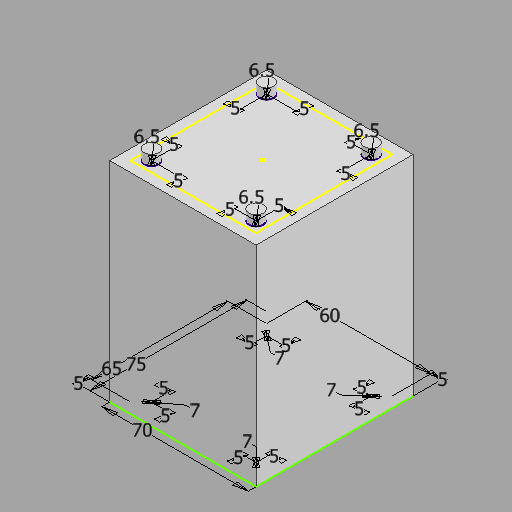
# Autodesk Inventor part: Z1
Saved by Autodesk Inventor 2027 (Build 310192000, 192)
## iProperties
Created: 2026-09-16
Part Number: Z1
Material: Generic
Document SubType Name: Modeling
Designer: jyjhm
Density: 1 g/cm^3
Appearance: Default
Author: jyjhm
Autodesk Inventor part; units mm, degrees
ref_plane "YZ Plane" through (0, 0, 0) normal (1, 0, 0) x (0, 1, 0)
ref_plane "XZ Plane" through (0, 0, 0) normal (0, 1, 0) x (-1, 0, 0)
ref_plane "XY Plane" through (0, 0, 0) normal (0, 0, 1) x (1, 0, 0)
sketch "Sketch1" plane through (0, 0, 0) normal (0, 1, 0) x (-1, 0, 0)
  line L0 (36.6667, 36.6667) -> (-33.3333, 36.6667)
  line L1 (-33.3333, 36.6667) -> (-33.3333, -38.3333)
  line L2 (-33.3333, -38.3333) -> (36.6667, -38.3333)
  line L3 (36.6667, -38.3333) -> (36.6667, 36.6667)
  line L4 (31.6667, 31.6667) -> (-28.3333, 31.6667)
  line L5 (-28.3333, 31.6667) -> (-28.3333, -33.3333)
  line L6 (-28.3333, -33.3333) -> (31.6667, -33.3333)
  line L7 (31.6667, -33.3333) -> (31.6667, 31.6667)
  circle A0 centre (26.6667, 26.6667) radius 3.5
  circle A1 centre (26.6667, -28.3333) radius 3.5
  circle A2 centre (-23.3333, -28.3333) radius 3.5
  circle A3 centre (-23.3333, 26.6667) radius 3.5
  point P0 (0, 0)
  dimension "d0" = 70
  dimension "d1" = 75
  dimension "d2" = 65
  dimension "d3" = 5
  dimension "d4" = 60
  dimension "d5" = 5
  dimension "d6" = 5
  dimension "d7" = 5
  dimension "d8" = 5
  dimension "d9" = 5
  dimension "d10" = 5
  dimension "d11" = 5
  dimension "d12" = 5
  dimension "d13" = 5
  dimension "d27" = 7
  dimension "d28" = 7
  dimension "d29" = 7
  dimension "d30" = 7
  constraints: 16 end point, 4 centre point, 4 parallel, 2 horizontal, 2 perpendicular
  measures "d0" distance of L0.start L0.end
  measures "d1" distance of L2.end L0.start
  measures "d2" distance of L6.end L4.start
  measures "d3" distance between parallel lines of L0 L4
  measures "d4" distance of L5.end L6.end
  measures "d5" distance between parallel lines of L1 L5
  measures "d6" distance from line of L7 A0.centre
  measures "d7" distance from line of L4 A0.centre
  measures "d8" distance from line of L5 A3.centre
  measures "d9" distance from line of L4 A3.centre
  measures "d10" distance from line of L6 A2.centre
  measures "d11" distance from line of L5 A2.centre
  measures "d12" distance from line of L6 A1.centre
  measures "d13" distance from line of L7 A1.centre
  measures "d27" diameter of A3
  measures "d28" diameter of A0
  measures "d29" diameter of A2
  measures "d30" diameter of A1
extrude "Extrusion1" add sketch "Sketch1" along normal blind 10 contours L3 L2 L1 L0 | L7 L6 L5 L4 | A0 | A1 | A2 | A3
extrude "Extrusion2" add sketch "Sketch1" along normal blind 100 contours L3 L2 L1 L0
sketch "Sketch2" plane through (0, 100, 0) normal (0, 1, 0) x (1, 0, 0)
  line L0 (33.3333, -36.6667) -> (33.3333, 38.3333) projected
  line L1 (33.3333, 38.3333) -> (-36.6667, 38.3333) projected
  line L2 (-36.6667, 38.3333) -> (-36.6667, -36.6667) projected
  line L3 (-36.6667, -36.6667) -> (33.3333, -36.6667) projected
  line L4 (-31.6667, -31.6667) -> (-31.6667, 33.3333) projected
  line L5 (-31.6667, 33.3333) -> (28.3333, 33.3333) projected
  line L6 (28.3333, 33.3333) -> (28.3333, -31.6667) projected
  line L7 (28.3333, -31.6667) -> (-31.6667, -31.6667) projected
  line L8 (-31.6667, -31.6667) -> (28.3333, -31.6667) projected
  line L9 (28.3333, -31.6667) -> (28.3333, 33.3333) projected
  line L10 (28.3333, 33.3333) -> (-31.6667, 33.3333) projected
  line L11 (-31.6667, 33.3333) -> (-31.6667, -31.6667) projected
  point P0 (0, 0)
extrude "Extrusion3" add sketch "Sketch2" against normal blind 10 contours L3 L2 L1 L0 | L4 L5 L6 L7
extrude "Extrusion4" cut sketch "Sketch1" along normal blind 5 contours A0 | A1 | A2 | A3
sketch "Sketch4" plane through (0, 100, 0) normal (0, 1, 0) x (1, 0, 0)
  line L0 (33.3333, 38.3333) -> (-36.6667, 38.3333) projected
  line L1 (-36.6667, 38.3333) -> (-36.6667, -36.6667) projected
  line L2 (-36.6667, 38.3333) -> (-36.6667, -36.6667) projected
  line L3 (33.3333, 38.3333) -> (-36.6667, 38.3333) projected
  line L4 (-31.6667, 33.3333) -> (-31.6667, -31.6667) projected
  line L5 (-31.6667, 33.3333) -> (-31.6667, -31.6667) projected
  line L6 (-31.6667, -31.6667) -> (28.3333, -31.6667) projected
  line L7 (-31.6667, -31.6667) -> (28.3333, -31.6667) projected
  line L8 (28.3333, 33.3333) -> (-31.6667, 33.3333) projected
  line L9 (28.3333, 33.3333) -> (-31.6667, 33.3333) projected
  line L10 (28.3333, -31.6667) -> (28.3333, 33.3333) projected
  line L11 (28.3333, -31.6667) -> (28.3333, 33.3333) projected
  line L12 (-36.6667, 38.3333) -> (-36.6667, -36.6667) projected
  line L13 (-36.6667, 38.3333) -> (-36.6667, -36.6667) projected
  line L14 (33.3333, 38.3333) -> (-36.6667, 38.3333) projected
  line L15 (33.3333, 38.3333) -> (-36.6667, 38.3333) projected
  line L16 (33.3333, -36.6667) -> (33.3333, 38.3333) projected
  line L17 (33.3333, -36.6667) -> (33.3333, 38.3333) projected
  line L18 (-36.6667, -36.6667) -> (33.3333, -36.6667) projected
  line L19 (-36.6667, -36.6667) -> (33.3333, -36.6667) projected
  line L20 (33.3333, -36.6667) -> (33.3333, 38.3333) projected
  line L21 (33.3333, 38.3333) -> (-36.6667, 38.3333) projected
  line L22 (-36.6667, 38.3333) -> (-36.6667, -36.6667) projected
  line L23 (-36.6667, -36.6667) -> (33.3333, -36.6667) projected
  line L24 (33.3333, -36.6667) -> (33.3333, 38.3333) projected
  line L25 (-36.6667, -36.6667) -> (33.3333, -36.6667) projected
  line L26 (-31.6667, 33.3333) -> (-31.6667, -31.6667) projected
  line L27 (-31.6667, -31.6667) -> (28.3333, -31.6667) projected
  line L28 (28.3333, 33.3333) -> (-31.6667, 33.3333) projected
  line L29 (28.3333, -31.6667) -> (28.3333, 33.3333) projected
  line L30 (28.3333, -31.6667) -> (28.3333, 33.3333) projected
  line L31 (-31.6667, -31.6667) -> (28.3333, -31.6667) projected
  line L32 (-31.6667, 33.3333) -> (-31.6667, -31.6667) projected
  line L33 (28.3333, 33.3333) -> (-31.6667, 33.3333) projected
  line L34 (-31.6667, -31.6667) -> (28.3333, -31.6667) projected
  line L35 (28.3333, -31.6667) -> (28.3333, 33.3333) projected
  circle A0 centre (-26.6667, -26.6667) radius 3.5 projected
  circle A1 centre (-26.6667, -26.6667) radius 3.5 projected
  circle A2 centre (-26.6667, -26.6667) radius 3.5 projected
  circle A3 centre (-26.6667, 28.3333) radius 3.5 projected
  circle A4 centre (23.3333, 28.3333) radius 3.5 projected
  circle A5 centre (23.3333, 28.3333) radius 3.5 projected
  line L36 (33.3333, -36.6667) -> (33.3333, 38.3333) projected
  circle A6 centre (-26.6667, 28.3333) radius 3.5 projected
  circle A7 centre (23.3333, 28.3333) radius 3.5 projected
  circle A8 centre (-26.6667, -26.6667) radius 3.5 projected
  circle A9 centre (23.3333, -26.6667) radius 3.5 projected
  line L37 (33.3333, -36.6667) -> (33.3333, 38.3333) projected
  line L38 (-36.6667, -36.6667) -> (33.3333, -36.6667) projected
  line L39 (-36.6667, 38.3333) -> (-36.6667, -36.6667) projected
  line L40 (33.3333, 38.3333) -> (-36.6667, 38.3333) projected
  line L41 (-36.6667, -36.6667) -> (33.3333, -36.6667) projected
  line L42 (-31.6667, -31.6667) -> (28.3333, -31.6667) projected
  line L43 (28.3333, -31.6667) -> (28.3333, 33.3333) projected
  line L44 (28.3333, 33.3333) -> (-31.6667, 33.3333) projected
  line L45 (-31.6667, 33.3333) -> (-31.6667, -31.6667) projected
  line L46 (-31.6667, 33.3333) -> (-31.6667, -31.6667) projected
  circle A10 centre (-26.6667, -26.6667) radius 3.5 projected
  circle A11 centre (-26.6667, -26.6667) radius 3.5 projected
  circle A12 centre (23.3333, -26.6667) radius 3.5 projected
  circle A13 centre (23.3333, -26.6667) radius 3.5 projected
  circle A14 centre (23.3333, -26.6667) radius 3.5 projected
  circle A15 centre (23.3333, -26.6667) radius 3.5 projected
  circle A16 centre (23.3333, -26.6667) radius 3.5 projected
  line L47 (28.3333, 33.3333) -> (-31.6667, 33.3333) projected
  circle A17 centre (23.3333, 28.3333) radius 3.5 projected
  circle A18 centre (23.3333, 28.3333) radius 3.5 projected
  circle A19 centre (23.3333, 28.3333) radius 3.5 projected
  circle A20 centre (-26.6667, 28.3333) radius 3.5 projected
  circle A21 centre (-26.6667, 28.3333) radius 3.5 projected
  circle A22 centre (-26.6667, 28.3333) radius 3.5 projected
  circle A23 centre (-26.6667, 28.3333) radius 3.5 projected
  circle A24 centre (-26.6667, 28.3333) radius 3.5 projected
  circle A25 centre (23.3333, -26.6667) radius 3.5 projected
  line L48 (-31.6667, -31.6667) -> (28.3333, -31.6667) projected
  line L49 (28.3333, -31.6667) -> (28.3333, 33.3333) projected
  line L50 (33.3333, -36.6667) -> (33.3333, 38.3333) projected
  line L51 (-36.6667, -36.6667) -> (33.3333, -36.6667) projected
  circle A26 centre (-26.6667, -26.6667) radius 3.5 projected
  line L52 (-31.6667, 33.3333) -> (-31.6667, -31.6667) projected
  line L53 (-36.6667, 38.3333) -> (-36.6667, -36.6667) projected
  circle A27 centre (23.3333, 28.3333) radius 3.5 projected
  line L54 (33.3333, 38.3333) -> (-36.6667, 38.3333) projected
  line L55 (28.3333, 33.3333) -> (-31.6667, 33.3333) projected
  point P0 (0, 0)
  point P1 (0, 0)
  constraints: 20 other
sketch "Sketch5" plane through (0, 100, 0) normal (0, 1, 0) x (1, 0, 0)
  circle A0 centre (23.3333, -26.6667) radius 3.25
  line L0 (-31.6667, -31.6667) -> (28.3333, -31.6667) projected
  line L1 (28.3333, -31.6667) -> (28.3333, 33.3333) projected
  circle A1 centre (-26.6667, -26.6667) radius 3.25
  circle A2 centre (23.3333, 28.3333) radius 3.25
  circle A3 centre (-26.6667, 28.3333) radius 3.25
  line L2 (-31.6667, 33.3333) -> (-31.6667, -31.6667) projected
  line L3 (28.3333, 33.3333) -> (-31.6667, 33.3333) projected
  point P0 (0, 0)
  dimension "d24" = 5
  dimension "d25" = 5
  dimension "d26" = 6.5
  dimension "d31" = 6.5
  dimension "d32" = 6.5
  dimension "d33" = 6.5
  dimension "d34" = 5
  dimension "d35" = 5
  dimension "d36" = 5
  dimension "d37" = 5
  dimension "d38" = 5
  dimension "d39" = 5
  constraints: 4 centre point
  measures "d24" distance from line of L0 A0.centre
  measures "d25" distance from line of L1 A0.centre
  measures "d26" diameter of A0
  measures "d31" diameter of A1
  measures "d32" diameter of A2
  measures "d33" diameter of A3
  measures "d34" distance from line of L0 A1.centre
  measures "d35" distance from line of L2 A1.centre
  measures "d36" distance from line of L2 A3.centre
  measures "d37" distance from line of L3 A3.centre
  measures "d38" distance from line of L3 A2.centre
  measures "d39" distance from line of L1 A2.centre
extrude "Extrusion5" add sketch "Sketch4" along normal blind 5 contours A0 | A3 | A4 | A9
body "Solid1"
